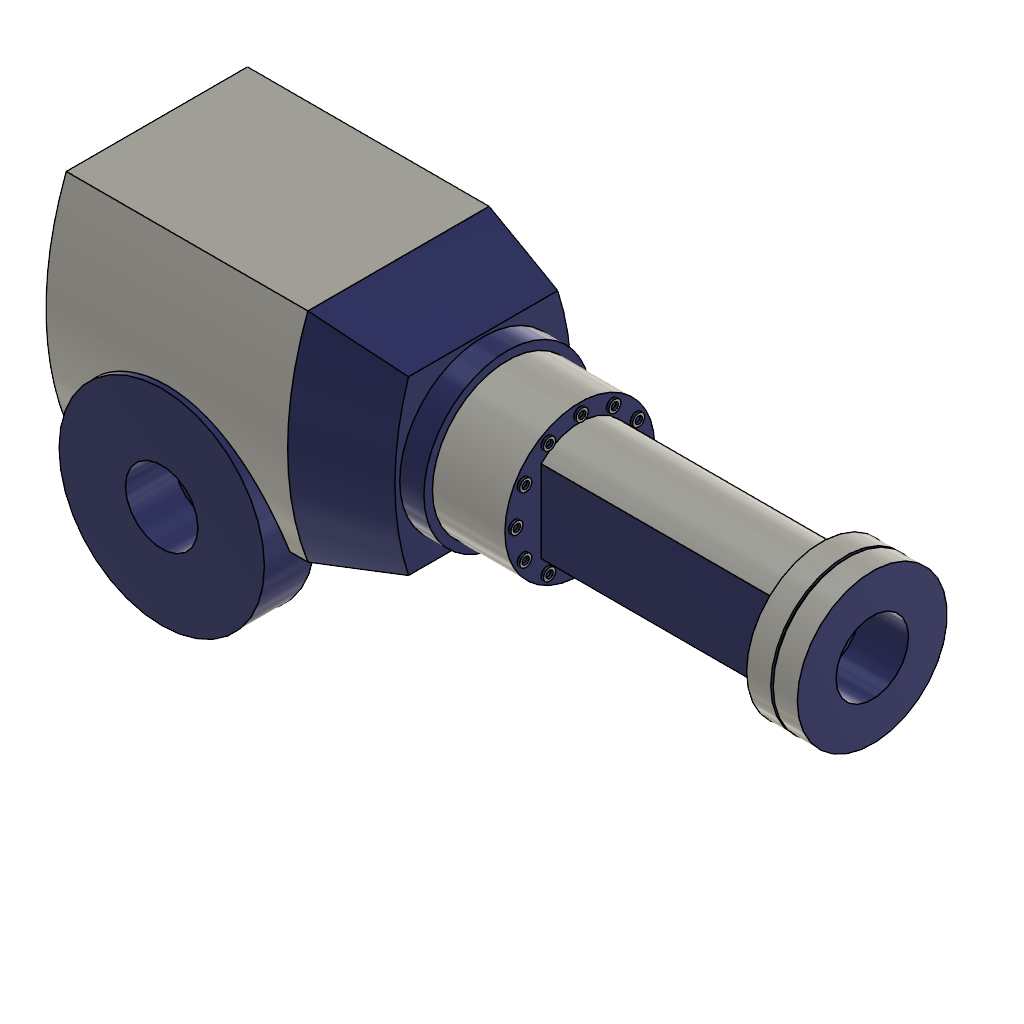
robotic_arm (Autodesk Fusion 360 archive; units mm, degrees)
design "jaw3"
part number: 2026-11-17-13-22-34-875
Autodesk Fusion 360 part; units mm, degrees
(part 1 of 2)
sketch "Esquisse1" plane through (0, 0, 0) normal (1, 0, 0) x (0, 1, 0)
  line L0 (0, 0) -> (0, 45)
  line L1 (0, 0) -> (0, -45)
  line L2 (0, 45) -> (37.5, 45)
  line L3 (0, 45) -> (-37.5, 45)
  line L4 (0, -45) -> (37.5, -45)
  line L5 (0, -45) -> (-37.5, -45)
  arc A0 (-37.5, 45) -> (-37.5, -45) centre (79.119, 0) ccw
  line L6 (0, 1.75) -> (0, 22.5)
  arc A1 (37.5, -45) -> (37.5, 45) centre (-79.119, 0) ccw
  dimension "d1" = 45
  dimension "d2" = 45
  dimension "d3" = 37.5
  dimension "d4" = 37.5
  dimension "d5" = 37.5
  dimension "d6" = 37.5
  dimension "d7" = 125
  constraint coincident L0.start L1.start
  constraint vertical L0
  constraint parallel L0 L1
  constraint perpendicular L0 L2
  constraint perpendicular L0 L3
  constraint perpendicular L1 L4
  constraint perpendicular L1 L5
  constraint symmetric L3.end L6 L2.end
  constraint symmetric L5.end L6 L4.end
  constraint symmetric A0 L6 A1
  measures "d1" distance of L0.start L0.end
  measures "d2" distance of L0.start L1.end
  measures "d3" distance of L0.end L2.end
  measures "d4" distance of L0.end L3.end
  measures "d5" distance of L1.end L4.end
  measures "d6" distance of L1.end L5.end
  measures "d7" radius of A0
extrude "Extrusion1" add sketch "Esquisse1" along normal blind 100
extrude "Extrusion2" add 1 faces at (100, -15.1807, -3.0661) along direction (1, 0, 0) blind 35 draft -15
sketch "Esquisse2" plane through (135, 0, 0) normal (1, 0, 0) x (0, 1, 0)
  line L0 (-30.8786, -35.6218) -> (30.8786, -35.6218)
  arc A0 (30.8786, -35.6218) -> (30.8786, 35.6218) centre (-79.119, 0) ccw
  line L1 (30.8786, 35.6218) -> (-30.8786, 35.6218)
  arc A1 (-30.8786, 35.6218) -> (-30.8786, -35.6218) centre (79.119, 0) ccw
  circle A2 centre (0, 0) radius 34.5
  dimension "d12" = 69
  constraint coincident A2.centre origin
  measures "d12" diameter of A2
extrude "Extrusion3" add sketch "Esquisse2" along normal blind 10 contours A2
sketch "Esquisse3" plane through (145, 0, 0) normal (1, 0, 0) x (0, 1, 0)
  circle A0 centre (0, 0) radius 34.5
  circle A1 centre (0, 0) radius 31
  dimension "d15" = 62
  constraint concentric A0 A1
  measures "d15" diameter of A1
extrude "Extrusion4" add sketch "Esquisse3" along normal blind 30 contours A1
sketch "Esquisse4" plane through (175, 0, 0) normal (1, 0, 0) x (0, 1, 0)
  circle A0 centre (0, 0) radius 31
  line L0 (0, 0) -> (27, 0) construction
  circle A1 centre (27, 0) radius 2.5
  circle A2 centre (27, 0) radius 1.5
  dimension "d18" = 27
  dimension "d19" = 5
  dimension "d20" = -1
  constraint coincident A0.centre L0.start
  constraint horizontal L0
  constraint coincident L0.end A1.centre
  measures "d18" distance of A0.centre L0.end
  measures "d19" diameter of A1
extrude "Extrusion5" add sketch "Esquisse4" along normal blind 1 contours A1
pattern_circular "Réseau C1" count 12 over 360 about axis through (175, 0, 0) along (1, 0, 0) of "Extrusion5"
sketch "Esquisse5" plane through (175, 0, 0) normal (1, 0, 0) x (0, 1, 0)
  circle A0 centre (27, 0) radius 2.5
  circle A1 centre (0, 0) radius 31
  circle A2 centre (23.3827, 13.5) radius 2.5
  circle A3 centre (13.5, 23.3827) radius 2.5
  circle A4 centre (0, 27) radius 2.5
  circle A5 centre (-13.5, 23.3827) radius 2.5
  circle A6 centre (-23.3827, 13.5) radius 2.5
  circle A7 centre (-27, 0) radius 2.5
  circle A8 centre (-23.3827, -13.5) radius 2.5
  circle A9 centre (-13.5, -23.3827) radius 2.5
  circle A10 centre (0, -27) radius 2.5
  circle A11 centre (13.5, -23.3827) radius 2.5
  circle A12 centre (23.3827, -13.5) radius 2.5
  line L0 (0, 0) -> (16, 0)
  line L1 (16, 0) -> (16, 17)
  line L2 (16, 0) -> (16, -17)
  line L3 (0, 1.75) -> (0, 22.5)
  line L4 (-16, 0) -> (-16, 17)
  line L5 (-16, 0) -> (-16, -17)
  arc A13 (16, 17) -> (-16, 17) centre (0, 1.9003) ccw
  line L6 (1.75, 0) -> (22.5, 0)
  arc A14 (-16, -17) -> (16, -17) centre (0, -1.9003) ccw
  dimension "d25" = 16
  dimension "d26" = 17
  dimension "d27" = 17
  dimension "d28" = 22
  constraint coincident A1.centre L0.start
  constraint horizontal L0
  constraint perpendicular L0 L1
  constraint perpendicular L0 L2
  constraint symmetric L0.end L3 L4.start
  constraint symmetric L1.end L3 L4.end
  constraint symmetric L2.end L3 L5.end
  constraint symmetric L1.end L6 L2.end
  constraint symmetric L4.end L6 L5.end
  constraint symmetric A13 L6 A14
  measures "d25" distance of A1.centre L0.end
  measures "d26" distance of L0.end L1.end
  measures "d27" distance of L0.end L2.end
  measures "d28" radius of A13
extrude "Extrusion6" add sketch "Esquisse5" along normal blind 100 contours L1 L2 L4 L5 A13 A14
sketch "Esquisse6" plane through (275, 0, 0) normal (1, 0, 0) x (0, 1, 0)
  line L0 (-16, 17) -> (-16, -17)
  arc A0 (-16, -17) -> (16, -17) centre (0, -1.9003) ccw
  line L1 (16, -17) -> (16, 17)
  arc A1 (16, 17) -> (-16, 17) centre (0, 1.9003) ccw
  circle A2 centre (0, 0) radius 31
extrude "Extrusion7" add sketch "Esquisse6" along normal blind 10 contours L0 A0 L1 A1 | A2
sketch "Esquisse7" plane through (285, 0, 0) normal (1, 0, 0) x (0, 1, 0)
  circle A0 centre (0, 0) radius 31
  circle A1 centre (0, 0) radius 30
  dimension "d33" = -1
extrude "Extrusion8" add sketch "Esquisse7" along normal blind 1 contours A1
sketch "Esquisse8" plane through (286, 0, 0) normal (1, 0, 0) x (0, 1, 0)
  circle A0 centre (0, 0) radius 30
  circle A1 centre (0, 0) radius 31
  dimension "d36" = 62
  constraint concentric A0 A1
  measures "d36" diameter of A1
extrude "Extrusion9" add sketch "Esquisse8" along normal blind 10 contours A0 | A1
ref_plane "Plan de construction1" through (0, -37.5, 45) normal (0, -1, 0) x (1, 0, 0)
sketch "Esquisse9" plane through (0, -37.5, 0) normal (0, -1, 0) x (-1, 0, 0)
  circle A0 centre (-50, 45) radius 42.5
  dimension "d40" = 85
  measures "d40" diameter of A0
extrude "Extrusion10" add sketch "Esquisse9" along normal mid plane 21
sketch "Esquisse10" plane through (0, -27, 0) normal (0, 1, 0) x (-1, 0, 0)
  line L0 (-7.5, -45) -> (-92.5, -45)
  arc A0 (-92.5, -45) -> (-7.5, -45) centre (-50, -45) ccw
  line L1 (-50, -45) -> (-50, -75) construction
  line L2 (-70, -45) -> (-70, -68.0897)
  line L3 (-30, -45) -> (-30, -68.0897)
  arc A1 (-70, -68.0897) -> (-30, -68.0897) centre (-50, -45.729) ccw
  dimension "d43" = 30
  dimension "d44" = 20
  dimension "d45" = -20
  dimension "d46" = 30
  constraint coincident A0.centre L1.start
  constraint perpendicular L0 L1
  measures "d43" distance of A0.centre L1.end
  measures "d46" radius of A1
extrude "Extrusion11" add sketch "Esquisse10" along normal blind 35 contours L0 L2 L3 A1
sketch "Esquisse11" plane through (70, 0, 0) normal (1, 0, 0) x (0, 1, 0)
  line L0 (-27, -45) -> (-27, -68.0897)
  line L1 (-27, -68.0897) -> (8, -68.0897)
  line L2 (8, -68.0897) -> (8, -45)
  line L3 (8, -45) -> (-27, -45)
  line L4 (8, -45) -> (33, -45)
  line L5 (8, -45) -> (8, -87)
  arc A0 (8, -87) -> (33, -45) centre (-21.8393, -40.7981) ccw
  dimension "d49" = 25
  dimension "d50" = 42
  dimension "d51" = 55
  constraint coincident L2.end L3.start
  constraint perpendicular L2 L4
  constraint perpendicular L3 L5
  measures "d49" distance of L2.end L4.end
  measures "d50" distance of L2.end L5.end
  measures "d51" radius of A0
extrude "Extrusion12" add sketch "Esquisse11" against normal blind 40 contours L2 L4 L5 A0
delete_face "DeleteFace1" 1 faces at (50, 8, -83.243)
sketch "Esquisse12" plane through (296, 0, 0) normal (1, 0, 0) x (0, 1, 0)
  circle A0 centre (0, 0) radius 31
  circle A1 centre (0, 0) radius 15
  dimension "d54" = 30
  constraint coincident A0.centre A1.centre
  measures "d54" diameter of A1
extrude "Extrusion13" cut sketch "Esquisse12" against normal blind 20 contours A1
sketch "Esquisse13" plane through (0, -48, 0) normal (0, -1, 0) x (1, 0, 0)
  circle A0 centre (50, -45) radius 42.5
  circle A1 centre (50, -45) radius 15
  dimension "d57" = 30
  constraint concentric A0 A1
  measures "d57" diameter of A1
extrude "Extrusion14" cut sketch "Esquisse13" against normal blind 20 contours A1
equation "d41 = ( 21 / 2 ) * 1 mm"

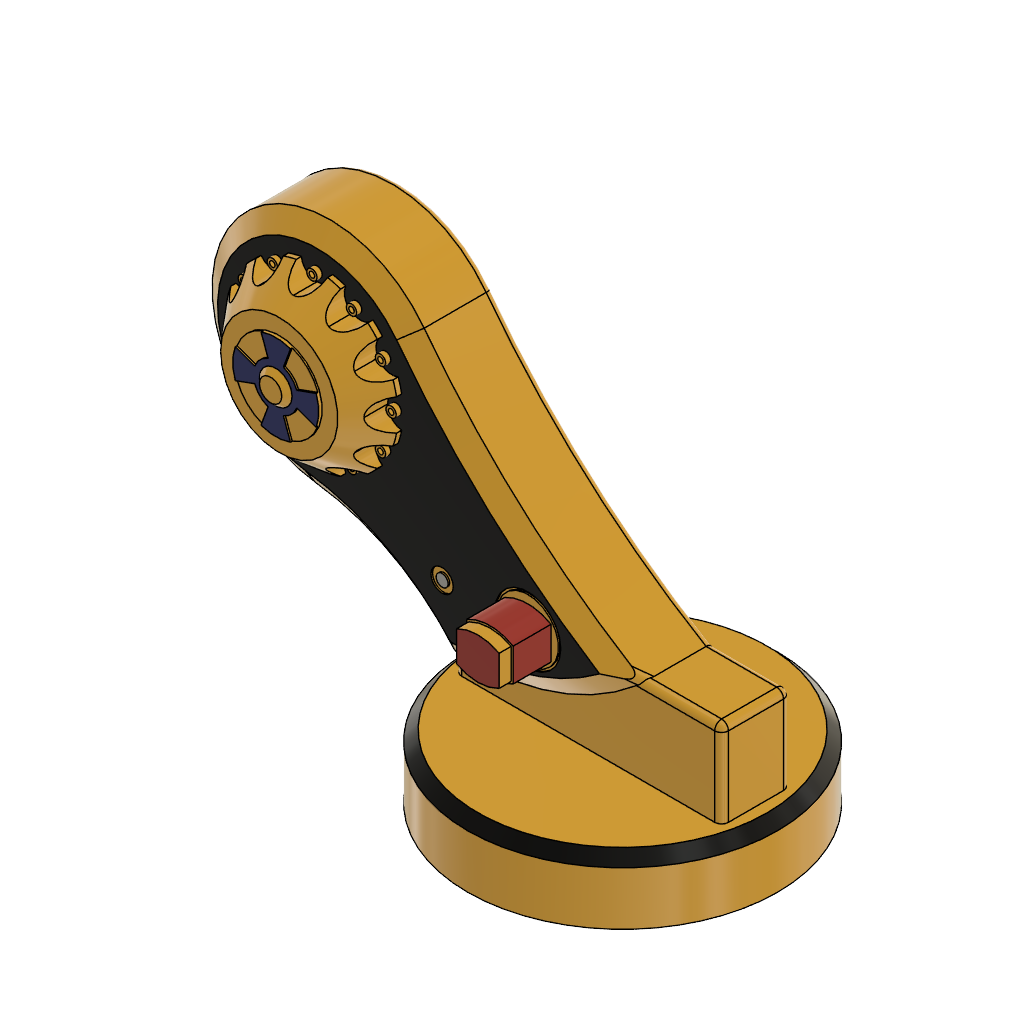
design "jaw"
part number: 2026-11-15-23-48-15-800
Autodesk Fusion 360 part; units mm, degrees
sketch "Esquisse8" plane through (0, 0, 0) normal (0, 0, 1) x (1, 0, 0)
  circle A0 centre (0, 0) radius 90
  dimension "d25" = 180
  constraint coincident A0.centre origin
  measures "d25" diameter of A0
extrude "Extrusion4" add sketch "Esquisse8" along normal blind 37
chamfer "Chanfrein2" distance 6 angle 45 1 edges at (-83.9095, -32.5454, 37) tangent chain off
sketch "Esquisse9" plane through (0, 0, 37) normal (0, 0, 1) x (-1, 0, 0)
  circle A0 centre (0, 0) radius 84
  line L0 (-77.5, 20) -> (77.5, 20)
  line L1 (77.5, 20) -> (77.5, -20)
  line L2 (77.5, -20) -> (-77.5, -20)
  line L3 (-77.5, -20) -> (-77.5, 20)
  line L4 (-77.5, 20) -> (77.5, -20) construction
  line L5 (77.5, 20) -> (-77.5, -20) construction
  dimension "d29" = 155
  dimension "d30" = 40
  constraint horizontal L0
  constraint perpendicular L0 L1
  constraint parallel L0 L2
  constraint parallel L1 L3
  constraint coincident L4 A0.centre
  constraint coincident L5 A0.centre
  constraint coincident A0.centre origin
  measures "d29" distance of L1.end L2.end
  measures "d30" distance of L0.end L1.end
extrude "Extrusion5" add sketch "Esquisse9" along normal blind 50 contours L0 L1 L2 L3
sketch "Esquisse10" plane through (0, -20, 0) normal (0, -1, 0) x (1, 0, 0)
  line L0 (-77.5, 37) -> (77.5, 37)
  line L1 (77.5, 37) -> (77.5, 87)
  line L2 (77.5, 87) -> (-77.5, 87)
  line L3 (-77.5, 87) -> (-77.5, 37)
  line L4 (-77.5, 87) -> (32.5, 87)
  line L5 (-77.5, 87) -> (-77.5, 48)
  arc A0 (-77.5, 48) -> (32.5, 87) centre (-68.6761, 197.7402) ccw
  dimension "d33" = 110
  dimension "d34" = 39
  dimension "d36" = 150
  constraint coincident L2.end L3.start
  constraint perpendicular L3 L4
  constraint perpendicular L2 L5
  measures "d33" distance of L2.end L4.end
  measures "d34" distance of L2.end L5.end
  measures "d36" radius of A0
extrude "Extrusion6" cut sketch "Esquisse10" against normal blind 125 contours L2 L3 L4 L5 A0
sketch "Esquisse12" plane through (0, 0, 0) normal (0, 1, 0) x (1, 0, 0)
  line L0 (0, 0) -> (-150, 0)
  line L1 (-150, 0) -> (-150, -160)
  circle A0 centre (-150, -160) radius 68.5
  arc A1 (32.5, -87) -> (-77.5, -48) centre (-68.6761, -197.7402) ccw
  arc A2 (-158.3154, -92.0066) -> (-77.5, -48) centre (-173.4894, 32.069) ccw
  arc A3 (32.5, -87) -> (-95.2795, -201.2057) centre (256.2101, -465.8849) ccw
  dimension "d39" = 150
  dimension "d40" = 160
  dimension "d41" = 137
  dimension "d42" = 125
  dimension "d43" = 440
  constraint coincident L0.start origin
  constraint horizontal L0
  constraint perpendicular L0 L1
  constraint coincident L1.end A0.centre
  constraint tangent A0 A2
  constraint coincident A1.end A2.end
  constraint coincident A0 A2.start
  constraint coincident A1.start A3.start
  constraint coincident A0 A3.end
  constraint tangent A0 A3
  measures "d39" distance of L0.start L0.end
  measures "d40" distance of L0.end L1.end
  measures "d41" diameter of A0
  measures "d42" radius of A2
  measures "d43" radius of A3
extrude "Extrusion9" add sketch "Esquisse12" along normal mid plane 40
sketch "Esquisse14" plane through (0, -20, 0) normal (0, -1, 0) x (1, 0, 0)
  line L0 (-77.5, 48) -> (-77.5, 37)
  line L1 (-77.5, 37) -> (77.5, 37)
  line L2 (77.5, 37) -> (77.5, 87)
  line L3 (77.5, 87) -> (32.5, 87)
  arc A0 (-95.2795, 201.2057) -> (32.5, 87) centre (256.2101, 465.8849) ccw
  arc A1 (-95.2795, 201.2057) -> (-158.3154, 92.0066) centre (-150, 160) ccw
  arc A2 (-77.5, 48) -> (-158.3154, 92.0066) centre (-173.4894, -32.069) ccw
  circle A3 centre (-150, 160) radius 68.5
  arc A4 (-77.5, 48) -> (32.5, 87) centre (-68.6761, 197.7402) ccw
  arc A5 (-95.2795, 201.2057) -> (32.5, 87) centre (256.2101, 465.8849) ccw
  arc A6 (-77.5, 48) -> (-158.3154, 92.0066) centre (-173.4894, -32.069) ccw
extrude "Extrusion10" add sketch "Esquisse14" along normal blind 7.5 draft -55 contours A0 A2 A3 A4 A5 A6 | A1 A3
sketch "Esquisse15" plane through (0, -27.5, 0) normal (0, -1, 0) x (1, 0, 0)
  arc A0 (-103.8359, 194.7625) -> (-157.0151, 102.6385) centre (-150, 160) ccw
  arc A1 (-72.4228, 58.5017) -> (-157.0151, 102.6385) centre (-173.4894, -32.069) ccw
  arc A2 (-72.4228, 58.5017) -> (14.1053, 85.7195) centre (-68.6761, 197.7402) ccw
  arc A3 (-103.8359, 194.7625) -> (14.1053, 85.7195) centre (256.2101, 465.8849) ccw
  circle A4 centre (-150, 160) radius 50
  dimension "d52" = 100
  constraint concentric A0 A4
  measures "d52" diameter of A4
extrude "Extrusion11" add sketch "Esquisse15" along normal blind 3 contours A4
extrude "Extrusion12" add 1 faces at (-167.3965, -30.5, 167.9656) along direction (0, -1, 0) blind 19 draft -40
sketch "Esquisse18" plane through (0, -49.5, 0) normal (0, -1, 0) x (1, 0, 0)
  circle A0 centre (-150, 160) radius 34.0571
  circle A1 centre (-150, 160) radius 50
  line L0 (-150, 160) -> (-150, 210)
  arc A2 (-159.1254, 209.1602) -> (-150, 201) centre (-150.1645, 209.9985) ccw
  arc A3 (-150, 201) -> (-140.8746, 209.1602) centre (-149.8355, 209.9985) ccw
  dimension "d62" = 9
  dimension "d63" = 9
  constraint coincident A0.centre A1.centre
  constraint coincident A1 L0.end
  constraint vertical L0
  constraint coincident A1 A2.start
  constraint coincident L0 A2.end
  constraint symmetric L0 A2.end A3.start
  constraint symmetric L0 A2.start A3.end
  constraint symmetric L0 A2 A3
  measures "d62" distance of L0.end A2.end
  measures "d63" radius of A2
extrude "Extrusion13" cut sketch "Esquisse18" against normal up to surface (22 mm away) contours A1 L0 A3 | A1 L0 A2
sketch "Esquisse19" plane through (0, -27.5, 0) normal (0, -1, 0) x (1, 0, 0)
  arc A0 (-159.1254, 209.1602) -> (-140.8746, 209.1602) centre (-150, 160) ccw
  arc A1 (-159.1254, 209.1602) -> (-150, 201) centre (-150.1645, 209.9985) ccw
  arc A2 (-150, 201) -> (-140.8746, 209.1602) centre (-149.8355, 209.9985) ccw
  arc A3 (-103.8359, 194.7625) -> (-157.0151, 102.6385) centre (-150, 160) ccw
  arc A4 (-72.4228, 58.5017) -> (-157.0151, 102.6385) centre (-173.4894, -32.069) ccw
  arc A5 (-72.4228, 58.5017) -> (14.1053, 85.7195) centre (-68.6761, 197.7402) ccw
  arc A6 (-103.8359, 194.7625) -> (14.1053, 85.7195) centre (256.2101, 465.8849) ccw
  line L0 (-150, 201) -> (-150, 217.7889)
  circle A7 centre (-150, 206) radius 3
  circle A8 centre (-150, 206) radius 1.6
  dimension "d66" = 6
  dimension "d67" = -1.4
  constraint coincident A1.end A2.start
  constraint coincident A3 L0.end
  constraint perpendicular A3 L0
  constraint coincident L0 A7.centre
  measures "d66" diameter of A7
extrude "Extrusion14" add sketch "Esquisse19" along normal blind 3 contours L0 A7 A8 | L0 A7 A8
pattern_circular "Réseau C1" count 12 over 360 about axis through (-150, -49.5, 160) along (0, 1, 0) of "Extrusion13", "Extrusion14"
sketch "Esquisse21" plane through (0, -49.5, 0) normal (0, -1, 0) x (1, 0, 0)
  circle A0 centre (-150, 160) radius 34.0571
  circle A1 centre (-150, 160) radius 13
  circle A2 centre (-150, 160) radius 25
  dimension "d72" = 26
  dimension "d73" = 50
  constraint concentric A0 A1
  constraint concentric A1 A2
  measures "d72" diameter of A1
  measures "d73" diameter of A2
extrude "Extrusion15" add sketch "Esquisse21" along normal blind 1 contours A1 | A2
sketch "Esquisse22" plane through (0, -50.5, 0) normal (0, -1, 0) x (1, 0, 0)
  circle A0 centre (-150, 160) radius 25
  circle A1 centre (-150, 160) radius 13
  line L0 (-149.9924, 173) -> (-149.9855, 185) construction
  line L1 (-158.5368, 183.4973) -> (-154.4392, 172.2186)
  line L2 (-141.4358, 183.4873) -> (-145.5466, 172.2134)
  line L3 (-173.4973, 151.4632) -> (-162.2186, 155.5608)
  line L4 (-173.4873, 168.5642) -> (-162.2134, 164.4534)
  line L5 (-141.4632, 136.5027) -> (-145.5608, 147.7814)
  line L6 (-158.5642, 136.5127) -> (-154.4534, 147.7866)
  line L7 (-126.5027, 168.5368) -> (-137.7814, 164.4392)
  line L8 (-126.5127, 151.4358) -> (-137.7866, 155.5466)
  dimension "d76" = 26
  dimension "d77" = 20
  dimension "d79" = 360
  constraint concentric A0 A1
  constraint coincident A1 L0.start
  constraint coincident A0 L0.end
  constraint perpendicular A0 L0
  constraint coincident A0 L1.start
  constraint coincident A1 L1.end
  constraint perpendicular A1 L1
  constraint symmetric L0 L1.start L2.start
  constraint symmetric L0 L1.end L2.end
  measures "d76" diameter of A1
  measures "d77" angle of L0 L1
extrude "Extrusion16" add sketch "Esquisse22" along normal blind 1 contours A0 A1 L7 L8 | A0 A1 L1 L2 | A1 | A0 A1 L5 L6 | A0 A1 L3 L4
sketch "Esquisse23" plane through (0, -51.5, 0) normal (0, -1, 0) x (1, 0, 0)
  line L0 (-126.5027, 168.5368) -> (-137.7814, 164.4392)
  arc A0 (-137.7814, 164.4392) -> (-145.5466, 172.2134) centre (-150, 160) ccw
  line L1 (-145.5466, 172.2134) -> (-141.4358, 183.4873)
  arc A1 (-141.4358, 183.4873) -> (-158.5368, 183.4973) centre (-150, 160) ccw
  line L2 (-158.5368, 183.4973) -> (-154.4392, 172.2186)
  arc A2 (-154.4392, 172.2186) -> (-162.2134, 164.4534) centre (-150, 160) ccw
  line L3 (-162.2134, 164.4534) -> (-173.4873, 168.5642)
  arc A3 (-173.4873, 168.5642) -> (-173.4973, 151.4632) centre (-150, 160) ccw
  line L4 (-173.4973, 151.4632) -> (-162.2186, 155.5608)
  arc A4 (-162.2186, 155.5608) -> (-154.4534, 147.7866) centre (-150, 160) ccw
  line L5 (-154.4534, 147.7866) -> (-158.5642, 136.5127)
  arc A5 (-158.5642, 136.5127) -> (-141.4632, 136.5027) centre (-150, 160) ccw
  line L6 (-141.4632, 136.5027) -> (-145.5608, 147.7814)
  arc A6 (-145.5608, 147.7814) -> (-137.7866, 155.5466) centre (-150, 160) ccw
  line L7 (-137.7866, 155.5466) -> (-126.5127, 151.4358)
  arc A7 (-126.5127, 151.4358) -> (-126.5027, 168.5368) centre (-150, 160) ccw
  circle A8 centre (-150, 160) radius 9.5
  dimension "d82" = 19
  constraint concentric A0 A8
  measures "d82" diameter of A8
extrude "Extrusion17" add sketch "Esquisse23" along normal blind 3 draft -45 contours A8
sketch "Esquisse24" plane through (0, -27.5, 0) normal (0, -1, 0) x (1, 0, 0)
  circle A0 centre (-150, 206) radius 3
  arc A1 (-133.3227, 207.1367) -> (-140.8746, 209.1602) centre (-150, 160) ccw
  arc A2 (-133.3227, 207.1367) -> (-129.5, 195.507) centre (-125.1432, 203.3822) ccw
  arc A3 (-129.5, 195.507) -> (-117.5171, 198.0113) centre (-124.8583, 203.2177) ccw
  arc A4 (-111.9887, 192.4829) -> (-117.5171, 198.0113) centre (-150, 160) ccw
  arc A5 (-111.9887, 192.4829) -> (-114.493, 180.5) centre (-106.7823, 185.1417) ccw
  arc A6 (-114.493, 180.5) -> (-102.8633, 176.6773) centre (-106.6178, 184.8568) ccw
  arc A7 (-100.8398, 169.1254) -> (-102.8633, 176.6773) centre (-150, 160) ccw
  arc A8 (-100.8398, 169.1254) -> (-109, 160) centre (-100.0015, 160.1645) ccw
  arc A9 (-109, 160) -> (-100.8398, 150.8746) centre (-100.0015, 159.8355) ccw
  arc A10 (-102.8633, 143.3227) -> (-100.8398, 150.8746) centre (-150, 160) ccw
  arc A11 (-102.8633, 143.3227) -> (-114.493, 139.5) centre (-106.6178, 135.1432) ccw
  arc A12 (-114.493, 139.5) -> (-111.9887, 127.5171) centre (-106.7823, 134.8583) ccw
  arc A13 (-117.5171, 121.9887) -> (-111.9887, 127.5171) centre (-150, 160) ccw
  arc A14 (-117.5171, 121.9887) -> (-129.5, 124.493) centre (-124.8583, 116.7823) ccw
  arc A15 (-129.5, 124.493) -> (-133.3227, 112.8633) centre (-125.1432, 116.6178) ccw
  arc A16 (-140.8746, 110.8398) -> (-133.3227, 112.8633) centre (-150, 160) ccw
  arc A17 (-140.8746, 110.8398) -> (-150, 119) centre (-149.8355, 110.0015) ccw
  arc A18 (-150, 119) -> (-159.1254, 110.8398) centre (-150.1645, 110.0015) ccw
  arc A19 (-166.6773, 112.8633) -> (-159.1254, 110.8398) centre (-150, 160) ccw
  arc A20 (-166.6773, 112.8633) -> (-170.5, 124.493) centre (-174.8568, 116.6178) ccw
  arc A21 (-170.5, 124.493) -> (-182.4829, 121.9887) centre (-175.1417, 116.7823) ccw
  arc A22 (-188.0113, 127.5171) -> (-182.4829, 121.9887) centre (-150, 160) ccw
  arc A23 (-188.0113, 127.5171) -> (-185.507, 139.5) centre (-193.2177, 134.8583) ccw
  arc A24 (-185.507, 139.5) -> (-197.1367, 143.3227) centre (-193.3822, 135.1432) ccw
  arc A25 (-199.1602, 150.8746) -> (-197.1367, 143.3227) centre (-150, 160) ccw
  arc A26 (-199.1602, 150.8746) -> (-191, 160) centre (-199.9985, 159.8355) ccw
  arc A27 (-191, 160) -> (-199.1602, 169.1254) centre (-199.9985, 160.1645) ccw
  arc A28 (-197.1367, 176.6773) -> (-199.1602, 169.1254) centre (-150, 160) ccw
  arc A29 (-197.1367, 176.6773) -> (-185.507, 180.5) centre (-193.3822, 184.8568) ccw
  arc A30 (-185.507, 180.5) -> (-188.0113, 192.4829) centre (-193.2177, 185.1417) ccw
  arc A31 (-182.4829, 198.0113) -> (-188.0113, 192.4829) centre (-150, 160) ccw
  arc A32 (-182.4829, 198.0113) -> (-170.5, 195.507) centre (-175.1417, 203.2177) ccw
  arc A33 (-170.5, 195.507) -> (-166.6773, 207.1367) centre (-174.8568, 203.3822) ccw
  arc A34 (-159.1254, 209.1602) -> (-166.6773, 207.1367) centre (-150, 160) ccw
  arc A35 (-159.1254, 209.1602) -> (-150, 201) centre (-150.1645, 209.9985) ccw
  arc A36 (-150, 201) -> (-140.8746, 209.1602) centre (-149.8355, 209.9985) ccw
  arc A37 (-103.8359, 194.7625) -> (-157.0151, 102.6385) centre (-150, 160) ccw
  arc A38 (-72.4228, 58.5017) -> (-157.0151, 102.6385) centre (-173.4894, -32.069) ccw
  arc A39 (-72.4228, 58.5017) -> (14.1053, 85.7195) centre (-68.6761, 197.7402) ccw
  arc A40 (-103.8359, 194.7625) -> (14.1053, 85.7195) centre (256.2101, 465.8849) ccw
  circle A41 centre (-127, 199.8372) radius 3
  circle A42 centre (-110.1628, 183) radius 3
  circle A43 centre (-104, 160) radius 3
  circle A44 centre (-110.1628, 137) radius 3
  circle A45 centre (-127, 120.1628) radius 3
  circle A46 centre (-150, 114) radius 3
  circle A47 centre (-173, 120.1628) radius 3
  circle A48 centre (-189.8372, 137) radius 3
  circle A49 centre (-196, 160) radius 3
  circle A50 centre (-189.8372, 183) radius 3
  circle A51 centre (-173, 199.8372) radius 3
  line L0 (-41.0792, 96.5795) -> (-14.0792, 96.5795)
  line L1 (-14.0792, 96.5795) -> (-14.0792, 77.5795)
  line L2 (-14.0792, 77.5795) -> (-41.0792, 77.5795)
  line L3 (-41.0792, 77.5795) -> (-41.0792, 96.5795)
  arc A52 (-14.0792, 96.5795) -> (-41.0792, 96.5795) centre (-27.5792, 73.1968) ccw
  arc A53 (-41.0792, 77.5795) -> (-14.0792, 77.5795) centre (-27.5792, 100.9622) ccw
  dimension "d85" = 27
  dimension "d86" = 19
  dimension "d87" = 27
  dimension "d88" = 27
  constraint horizontal L0
  constraint vertical L1
  constraint horizontal L2
  constraint vertical L3
  measures "d85" distance of L0.start L0.end
  measures "d86" distance of L0.start L2.end
  measures "d87" radius of A53
  measures "d88" radius of A52
extrude "Extrusion18" add sketch "Esquisse24" along normal blind 22 contours L0 A52 | L0 L1 L2 L3 | L2 A53
sketch "Esquisse25" plane through (0, -49.5, 0) normal (0, -1, 0) x (1, 0, 0)
  arc A0 (-14.0792, 96.5795) -> (-41.0792, 96.5795) centre (-27.5792, 73.1968) ccw
  line L0 (-41.0792, 96.5795) -> (-41.0792, 77.5795)
  arc A1 (-41.0792, 77.5795) -> (-14.0792, 77.5795) centre (-27.5792, 100.9622) ccw
  line L1 (-14.0792, 77.5795) -> (-14.0792, 96.5795)
  line L2 (-15.2302, 78.2538) -> (-15.2302, 95.9053)
  arc A2 (-15.2302, 95.9053) -> (-39.9282, 95.9053) centre (-27.5792, 73.1968) ccw
  line L3 (-39.9282, 95.9053) -> (-39.9282, 78.2538)
  arc A3 (-39.9282, 78.2538) -> (-15.2302, 78.2538) centre (-27.5792, 100.9622) ccw
  dimension "d91" = -1.151
extrude "Extrusion19" add sketch "Esquisse25" along normal blind 7 contours L2 A2 L3 A3
sketch "Esquisse26" plane through (0, -27.5, 0) normal (0, -1, 0) x (1, 0, 0)
  circle A0 centre (-173, 199.8372) radius 3
  circle A1 centre (-189.8372, 183) radius 3
  circle A2 centre (-196, 160) radius 3
  circle A3 centre (-189.8372, 137) radius 3
  circle A4 centre (-173, 120.1628) radius 3
  circle A5 centre (-150, 114) radius 3
  circle A6 centre (-127, 120.1628) radius 3
  circle A7 centre (-110.1628, 137) radius 3
  circle A8 centre (-104, 160) radius 3
  circle A9 centre (-110.1628, 183) radius 3
  circle A10 centre (-127, 199.8372) radius 3
  arc A11 (-103.8359, 194.7625) -> (-157.0151, 102.6385) centre (-150, 160) ccw
  arc A12 (-72.4228, 58.5017) -> (-157.0151, 102.6385) centre (-173.4894, -32.069) ccw
  arc A13 (-72.4228, 58.5017) -> (14.1053, 85.7195) centre (-68.6761, 197.7402) ccw
  arc A14 (-103.8359, 194.7625) -> (14.1053, 85.7195) centre (256.2101, 465.8849) ccw
  arc A15 (-133.3227, 207.1367) -> (-140.8746, 209.1602) centre (-150, 160) ccw
  arc A16 (-133.3227, 207.1367) -> (-129.5, 195.507) centre (-125.1432, 203.3822) ccw
  arc A17 (-129.5, 195.507) -> (-117.5171, 198.0113) centre (-124.8583, 203.2177) ccw
  arc A18 (-111.9887, 192.4829) -> (-117.5171, 198.0113) centre (-150, 160) ccw
  arc A19 (-111.9887, 192.4829) -> (-114.493, 180.5) centre (-106.7823, 185.1417) ccw
  arc A20 (-114.493, 180.5) -> (-102.8633, 176.6773) centre (-106.6178, 184.8568) ccw
  arc A21 (-100.8398, 169.1254) -> (-102.8633, 176.6773) centre (-150, 160) ccw
  arc A22 (-100.8398, 169.1254) -> (-109, 160) centre (-100.0015, 160.1645) ccw
  arc A23 (-109, 160) -> (-100.8398, 150.8746) centre (-100.0015, 159.8355) ccw
  arc A24 (-102.8633, 143.3227) -> (-100.8398, 150.8746) centre (-150, 160) ccw
  arc A25 (-102.8633, 143.3227) -> (-114.493, 139.5) centre (-106.6178, 135.1432) ccw
  arc A26 (-114.493, 139.5) -> (-111.9887, 127.5171) centre (-106.7823, 134.8583) ccw
  arc A27 (-117.5171, 121.9887) -> (-111.9887, 127.5171) centre (-150, 160) ccw
  arc A28 (-117.5171, 121.9887) -> (-129.5, 124.493) centre (-124.8583, 116.7823) ccw
  arc A29 (-129.5, 124.493) -> (-133.3227, 112.8633) centre (-125.1432, 116.6178) ccw
  arc A30 (-140.8746, 110.8398) -> (-133.3227, 112.8633) centre (-150, 160) ccw
  arc A31 (-140.8746, 110.8398) -> (-150, 119) centre (-149.8355, 110.0015) ccw
  arc A32 (-150, 119) -> (-159.1254, 110.8398) centre (-150.1645, 110.0015) ccw
  arc A33 (-166.6773, 112.8633) -> (-159.1254, 110.8398) centre (-150, 160) ccw
  arc A34 (-166.6773, 112.8633) -> (-170.5, 124.493) centre (-174.8568, 116.6178) ccw
  arc A35 (-170.5, 124.493) -> (-182.4829, 121.9887) centre (-175.1417, 116.7823) ccw
  arc A36 (-188.0113, 127.5171) -> (-182.4829, 121.9887) centre (-150, 160) ccw
  arc A37 (-188.0113, 127.5171) -> (-185.507, 139.5) centre (-193.2177, 134.8583) ccw
  arc A38 (-185.507, 139.5) -> (-197.1367, 143.3227) centre (-193.3822, 135.1432) ccw
  arc A39 (-199.1602, 150.8746) -> (-197.1367, 143.3227) centre (-150, 160) ccw
  arc A40 (-199.1602, 150.8746) -> (-191, 160) centre (-199.9985, 159.8355) ccw
  arc A41 (-191, 160) -> (-199.1602, 169.1254) centre (-199.9985, 160.1645) ccw
  arc A42 (-197.1367, 176.6773) -> (-199.1602, 169.1254) centre (-150, 160) ccw
  arc A43 (-197.1367, 176.6773) -> (-185.507, 180.5) centre (-193.3822, 184.8568) ccw
  arc A44 (-185.507, 180.5) -> (-188.0113, 192.4829) centre (-193.2177, 185.1417) ccw
  arc A45 (-182.4829, 198.0113) -> (-188.0113, 192.4829) centre (-150, 160) ccw
  arc A46 (-182.4829, 198.0113) -> (-170.5, 195.507) centre (-175.1417, 203.2177) ccw
  arc A47 (-170.5, 195.507) -> (-166.6773, 207.1367) centre (-174.8568, 203.3822) ccw
  arc A48 (-159.1254, 209.1602) -> (-166.6773, 207.1367) centre (-150, 160) ccw
  arc A49 (-159.1254, 209.1602) -> (-150, 201) centre (-150.1645, 209.9985) ccw
  arc A50 (-150, 201) -> (-140.8746, 209.1602) centre (-149.8355, 209.9985) ccw
  circle A51 centre (-150, 206) radius 3
  line L0 (-14.0792, 96.5795) -> (-14.0792, 77.5795)
  arc A52 (-41.0792, 77.5795) -> (-14.0792, 77.5795) centre (-27.5792, 100.9622) ccw
  line L1 (-41.0792, 77.5795) -> (-41.0792, 96.5795)
  arc A53 (-14.0792, 96.5795) -> (-41.0792, 96.5795) centre (-27.5792, 73.1968) ccw
  line L2 (-41.0792, 77.5795) -> (-14.0792, 96.5795)
  circle A54 centre (-27.5792, 87.0795) radius 17.857
  circle A55 centre (-27.5792, 87.0795) radius 19.1735
  line L3 (-27.5792, 87.0795) -> (-77.3464, 87.0795) construction
  circle A56 centre (-77.3464, 87.0795) radius 6.5
  circle A57 centre (-77.3464, 87.0795) radius 3.5
  dimension "d94" = 35.714
  dimension "d95" = 38.347
  dimension "d96" = 13
  dimension "d97" = 7
  constraint coincident A52.start L1.start
  constraint coincident L0.start A53.start
  constraint midpoint L2 A54.centre
  constraint concentric A54 A55
  constraint coincident A54.centre A55.centre
  constraint horizontal L3
  constraint coincident L3.end A56.centre
  measures "d94" diameter of A54
  measures "d95" diameter of A55
  measures "d96" diameter of A56
  measures "d97" diameter of A57
extrude "Extrusion20" cut sketch "Esquisse26" against normal blind 0.9 contours A55 | A56
sketch "Esquisse27" plane through (0, 0, 0) normal (0, 0, -1) x (1, 0, 0)
  circle A0 centre (0, 0) radius 90
  circle A1 centre (0, 0) radius 15
  dimension "d100" = 30
  constraint coincident A0.centre A1.centre
  measures "d100" diameter of A1
extrude "Extrusion21" cut sketch "Esquisse27" against normal blind 20 contours A1
fillet "Congé1" radius 4 10 edges at (55, -20, 87) (77.5, 0, 87) (77.5, -20, 62) (77.5, 20, 62) (55, 20, 87) (-113.7109, 20, 77.7105) (-209.3252, 20, 194.2458) (-37.0038, 20, 137.8215) (-77.5, 20, 42.5) (-77.5, -20, 42.5)
fillet "Congé2" radius 4 1 edges at (33.3618, -19.3305, 86.4926)
sketch "Esquisse28" plane through (0, 20, 0) normal (0, 1, 0) x (-1, 0, 0)
  line L0 (-73.5, 83) -> (-73.5, 37)
  line L1 (-73.5, 37) -> (73.5, 37)
  line L2 (73.5, 37) -> (73.5, 49.4364)
  arc A0 (157.8298, 95.977) -> (73.5, 49.4364) centre (173.4894, -32.069) ccw
  arc A1 (157.8298, 95.977) -> (98.4748, 198.7996) centre (150, 160) ccw
  arc A2 (-31.4099, 83) -> (98.4748, 198.7996) centre (-256.2101, 465.8849) ccw
  line L3 (-31.4099, 83) -> (-73.5, 83)
  circle A3 centre (150, 160) radius 15
  dimension "d107" = 30
  constraint concentric A1 A3
  measures "d107" diameter of A3
extrude "Extrusion22" cut sketch "Esquisse28" against normal blind 20 contours A3

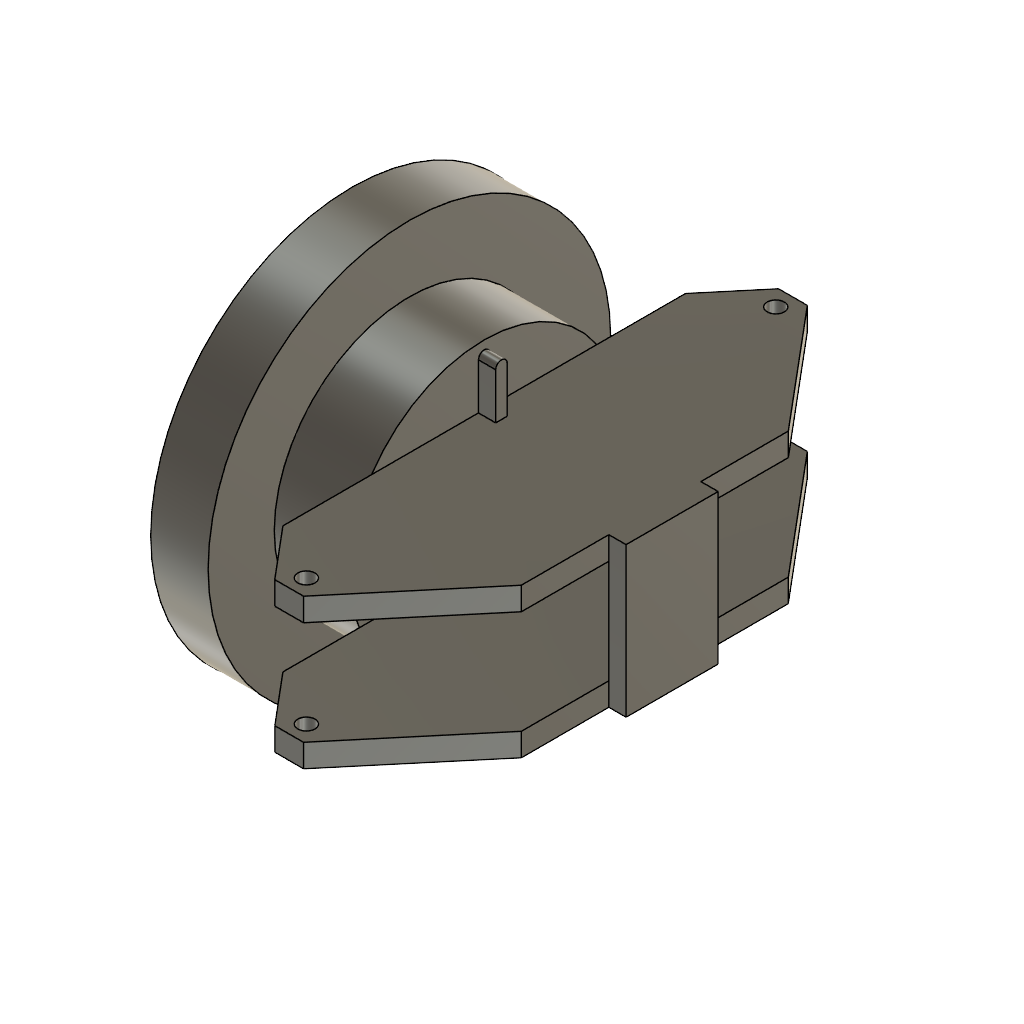
design "jaw6"
part number: 2026-11-18-08-03-36-471
Autodesk Fusion 360 part; units mm, degrees
sketch "Esquisse1" plane through (0, 0, 0) normal (1, 0, 0) x (0, 1, 0)
  circle A0 centre (0, 0) radius 35
  dimension "d1" = 70
  constraint coincident A0.centre origin
  measures "d1" diameter of A0
extrude "Extrusion1" add sketch "Esquisse1" along normal blind 10
sketch "Esquisse2" plane through (10, 0, 0) normal (1, 0, 0) x (0, 1, 0)
  circle A0 centre (0, 0) radius 35
  circle A1 centre (0, 0) radius 23.5
  dimension "d4" = 47
  constraint coincident A0.centre A1.centre
  measures "d4" diameter of A1
extrude "Extrusion2" add sketch "Esquisse2" along normal blind 13 contours A1
ref_plane "Plan de construction1" through (0, 0, 13) normal (0, 0, 1) x (1, 0, 0)
sketch "Esquisse3" plane through (0, 0, 13) normal (0, 0, 1) x (1, 0, 0)
  line L0 (23, 0) -> (23, -35)
  line L1 (23, -35) -> (30.3921, -43.8095)
  line L2 (30.3921, -43.8095) -> (35.3921, -43.8095)
  line L3 (23, 0) -> (52.6735, 0)
  line L4 (35.3921, -43.8095) -> (52.6735, -23.2143)
  line L5 (35.3921, -43.8095) -> (51.7524, -43.8095)
  line L6 (52.6735, -23.2143) -> (52.6735, 0)
  line L7 (23, 35) -> (30.3921, 43.8095)
  line L8 (30.3921, 43.8095) -> (35.3921, 43.8095)
  line L9 (35.3921, 43.8095) -> (52.6735, 23.2143)
  line L10 (52.6735, 23.2143) -> (52.6735, 0)
  line L11 (23, 0) -> (23, 35)
  dimension "d9" = 35
  dimension "d11" = 11.5
  dimension "d13" = 5
  dimension "d14" = 50
  constraint vertical L0
  constraint horizontal L2
  constraint perpendicular L0 L3
  constraint parallel L2 L5
  constraint perpendicular L3 L6
  constraint symmetric L0.start L3 L11.start
  constraint symmetric L0.end L3 L7.start
  constraint symmetric L1.end L3 L7.end
  constraint symmetric L2.end L3 L8.end
  constraint symmetric L3 L4.end L9.end
  measures "d9" distance of L0.start L0.end
  measures "d11" distance of L0.end L1.end
  measures "d13" distance of L1.end L2.end
  measures "d14" angle of L4 L5
extrude "Extrusion3" add sketch "Esquisse3" against normal blind 4
sketch "Esquisse4" plane through (0, 0, 13) normal (0, 0, 1) x (-1, 0, 0)
  line L0 (-23, 35) -> (-30.3921, 43.8095)
  line L1 (-30.3921, 43.8095) -> (-35.3921, 43.8095)
  line L2 (-35.3921, 43.8095) -> (-52.6735, 23.2143)
  line L3 (-52.6735, 23.2143) -> (-52.6735, -23.2143)
  line L4 (-52.6735, -23.2143) -> (-35.3921, -43.8095)
  line L5 (-35.3921, -43.8095) -> (-30.3921, -43.8095)
  line L6 (-30.3921, -43.8095) -> (-23, -35)
  line L7 (-23, -35) -> (-23, -19.5768)
  line L8 (-23, -19.5768) -> (-23, 19.5768)
  line L9 (-23, 19.5768) -> (-23, 35)
  line L10 (-32.8921, 43.8095) -> (-32.8921, 40.8095)
  circle A0 centre (-32.8921, 40.8095) radius 1.5
  dimension "d17" = 3
  dimension "d18" = 3
  constraint midpoint L1 L10.start
  constraint perpendicular L1 L10
  constraint coincident L10.end A0.centre
  measures "d17" distance of L10.start L10.end
  measures "d18" diameter of A0
extrude "Extrusion4" cut sketch "Esquisse4" against normal blind 12 contours A0
mirror "Symétrie miroir1" about plane through (0, 0, 0) normal (0, 1, 0) of "Extrusion4"
mirror "Symétrie miroir2" about plane through (0, 0, 0) normal (0, 0, 1) of "Extrusion3", "Extrusion4", "Symétrie miroir1"
sketch "Esquisse5" plane through (23, 0, 0) normal (1, 0, 0) x (0, 1, 0)
  line L0 (-19.5768, 13) -> (19.5768, 13)
  arc A0 (19.5768, 13) -> (-19.5768, 13) centre (0, 0) ccw
  line L1 (0, 13) -> (0, 23.5)
  line L2 (0, 13) -> (-1, 13)
  line L3 (-1, 13) -> (-1, 22)
  line L4 (-1, 22) -> (1, 22)
  line L5 (1, 22) -> (1, 13)
  dimension "d25" = 1
  dimension "d26" = 9
  dimension "d27" = 2
  constraint midpoint L0 L1.start
  constraint midpoint A0 L1.end
  constraint perpendicular L1 L2
  constraint perpendicular L0 L3
  constraint perpendicular L1 L4
  constraint coincident L0 L5.end
  constraint perpendicular L0 L5
  measures "d25" distance of L1.start L2.end
  measures "d26" distance of L2.end L3.end
  measures "d27" distance of L3.end L4.end
extrude "Extrusion5" add sketch "Esquisse5" along normal blind 3 contours L0 L1 L2 L3 L4 | L0 L1 L4 L5
fillet "Congé1" radius 1 2 edges at (24.5, -1, 22) (24.5, 1, 22)
mirror "Symétrie miroir3" about plane through (0, 0, 0) normal (0, 0, 1) of "Extrusion5", "Congé1"
sketch "Esquisse6" plane through (52.6735, 0, 0) normal (1, 0, 0) x (0, 1, 0)
  line L0 (23.2143, 13) -> (-23.2143, 13)
  line L1 (-23.2143, 13) -> (-23.2143, 9)
  line L2 (-23.2143, 9) -> (23.2143, 9)
  line L3 (23.2143, 9) -> (23.2143, 13)
  line L4 (8, -13) -> (-8, -13)
  line L5 (-8, -13) -> (-8, 13)
  line L6 (-8, 13) -> (8, 13)
  line L7 (8, 13) -> (8, -13)
  line L8 (8, -13) -> (-8, 13) construction
  line L9 (-8, -13) -> (8, 13) construction
  dimension "d34" = 16
  dimension "d35" = 26
  constraint horizontal L4
  constraint perpendicular L4 L5
  constraint parallel L4 L6
  constraint parallel L5 L7
  constraint coincident L8 origin
  constraint coincident L9 origin
  measures "d34" distance of L5.end L6.end
  measures "d35" distance of L4.end L5.end
extrude "Extrusion6" add sketch "Esquisse6" along normal blind 3 contours L0 L2 L5 L6 L7 | L2 L4 L5 L7
sketch "Esquisse7" plane through (0, 0, 0) normal (-1, 0, 0) x (0, -1, 0)
  circle A0 centre (0, 0) radius 35
  circle A1 centre (0, 0) radius 10
  dimension "d38" = 20
  constraint coincident A0.centre A1.centre
  measures "d38" diameter of A1
extrude "Extrusion7" cut sketch "Esquisse7" against normal blind 10 contours A1
equation "d4 = ( 23.5 * 2 ) * 1 mm"

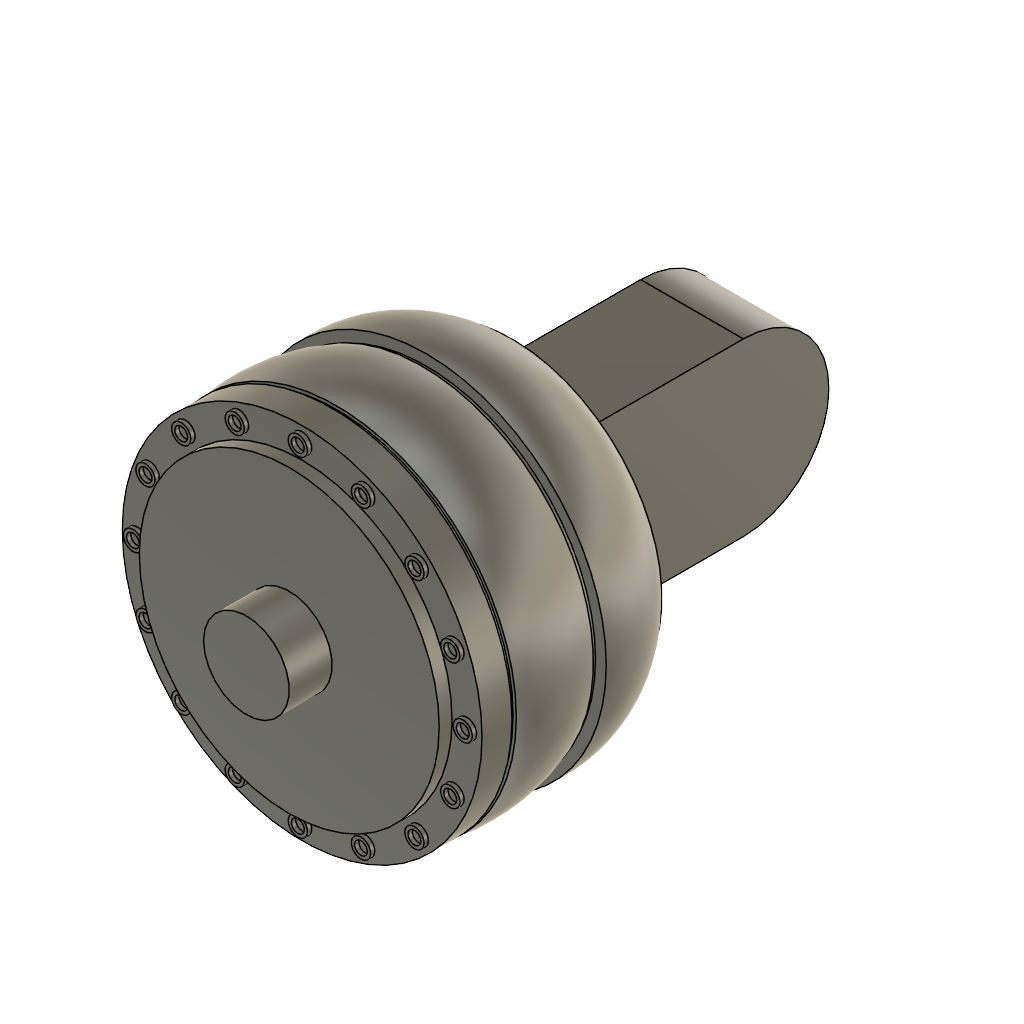
design "jaw5"
part number: 2026-11-17-17-52-57-447
Autodesk Fusion 360 part; units mm, degrees
sketch "Esquisse1" plane through (0, 0, 0) normal (0, 0, 1) x (1, 0, 0)
  line L0 (0, 0) -> (-35, 0)
  line L1 (0, 0) -> (0, -20)
  line L2 (0, -20) -> (-42, -20)
  arc A0 (-35, 0) -> (-42, -20) centre (-17.1273, -17.4804) ccw
  dimension "d1" = 35
  dimension "d2" = 20
  dimension "d3" = 42
  dimension "d4" = 25
  constraint coincident L0.start L1.start
  constraint horizontal L0
  constraint perpendicular L0 L1
  constraint perpendicular L1 L2
  measures "d1" distance of L0.start L0.end
  measures "d2" distance of L0.start L1.end
  measures "d3" distance of L1.end L2.end
  measures "d4" radius of A0
revolve "Révolution1" add sketch "Esquisse1" angle 360 about axis through (0, 0, 0) along (0, -1, 0)
sketch "Esquisse2" plane through (0, -20, 0) normal (0, -1, 0) x (1, 0, 0)
  circle A0 centre (0, 0) radius 42
  circle A1 centre (0, 0) radius 39.5
  dimension "d6" = 79
  constraint concentric A0 A1
  measures "d6" diameter of A1
extrude "Extrusion1" add sketch "Esquisse2" along normal blind 1 contours A1
sketch "Esquisse3" plane through (0, 0, 0) normal (0, 0, 1) x (1, 0, 0)
  line L0 (-39.5, -21) -> (39.5, -21)
  line L1 (0, -21) -> (0, -41)
  line L2 (0, -21) -> (-40, -21)
  line L3 (0, -41) -> (-42, -41)
  arc A0 (-40, -21) -> (-42, -41) centre (-5.5677, -34.5432) ccw
  dimension "d9" = 20
  dimension "d10" = 40
  dimension "d11" = 37
  constraint midpoint L0 L1.start
  constraint perpendicular L0 L1
  constraint perpendicular L1 L2
  constraint perpendicular L1 L3
  measures "d9" distance of L1.start L1.end
  measures "d10" distance of L1.start L2.end
  measures "d11" radius of A0
revolve "Révolution2" add sketch "Esquisse3" angle 360 about axis through (0, -21, 0) along (0, -1, 0)
sketch "Esquisse4" plane through (0, -41, 0) normal (0, -1, 0) x (1, 0, 0)
  circle A0 centre (0, 0) radius 42
  circle A1 centre (0, 0) radius 41.25
  dimension "d13" = 82.5
  constraint coincident A0.centre A1.centre
  measures "d13" diameter of A1
extrude "Extrusion2" add sketch "Esquisse4" along normal blind 1 contours A1
sketch "Esquisse5" plane through (0, -42, 0) normal (0, -1, 0) x (1, 0, 0)
  circle A0 centre (0, 0) radius 41.25
  circle A1 centre (0, 0) radius 42
  dimension "d16" = 84
  constraint concentric A0 A1
  measures "d16" diameter of A1
extrude "Extrusion3" add sketch "Esquisse5" along normal blind 7 contours A0 | A1
sketch "Esquisse6" plane through (0, -49, 0) normal (0, -1, 0) x (1, 0, 0)
  circle A0 centre (0, 0) radius 42
  circle A1 centre (0, 0) radius 35
  dimension "d19" = 70
  constraint coincident A0.centre A1.centre
  measures "d19" diameter of A1
extrude "Extrusion4" add sketch "Esquisse6" along normal blind 3 contours A1
sketch "Esquisse7" plane through (0, -49, 0) normal (0, -1, 0) x (1, 0, 0)
  circle A0 centre (0, 0) radius 35
  circle A1 centre (0, 0) radius 42
  line L0 (0, 0) -> (35, 0)
  line L1 (35, 0) -> (42, 0)
  circle A2 centre (38.5, 0) radius 2.25
  circle A3 centre (38.5, 0) radius 1.5
  dimension "d22" = 4.5
  dimension "d23" = 3
  constraint coincident A0.centre A1.centre
  constraint coincident A0 L0.end
  constraint horizontal L0
  constraint coincident A1 L1.end
  constraint perpendicular A1 L1
  constraint midpoint L1 A2.centre
  constraint concentric A2 A3
  measures "d22" diameter of A2
  measures "d23" diameter of A3
extrude "Extrusion5" add sketch "Esquisse7" along normal blind 1 contours L1 A2 A3 | L1 A2 A3
pattern_circular "Réseau C1" count 16 over 360 about axis through (0, -52, 0) along (0, -1, 0) of "Extrusion5"
sketch "Esquisse8" plane through (0, 0, 0) normal (0, 1, 0) x (-1, 0, 0)
  circle A0 centre (0, 0) radius 35
  line L0 (12, -20) -> (-12, -20)
  line L1 (-12, -20) -> (-12, 20)
  line L2 (-12, 20) -> (12, 20)
  line L3 (12, 20) -> (12, -20)
  line L4 (12, -20) -> (-12, 20) construction
  line L5 (-12, -20) -> (12, 20) construction
  dimension "d28" = 24
  dimension "d29" = 40
  constraint horizontal L0
  constraint perpendicular L0 L1
  constraint parallel L0 L2
  constraint parallel L1 L3
  constraint coincident L4 A0.centre
  constraint coincident L5 A0.centre
  constraint coincident A0.centre origin
  measures "d28" distance of L1.end L2.end
  measures "d29" distance of L0.end L1.end
extrude "Extrusion6" add sketch "Esquisse8" along normal blind 42 contours L0 L1 L2 L3
sketch "Esquisse9" plane through (12, 0, 0) normal (1, 0, 0) x (0, 1, 0)
  line L0 (0, 20) -> (0, -20)
  line L1 (0, -20) -> (42, -20)
  line L2 (42, -20) -> (42, 20)
  line L3 (42, 20) -> (0, 20)
  circle A0 centre (42, 0) radius 20
  constraint midpoint L2 A0.centre
  constraint coincident L1.end A0
extrude "Extrusion7" add sketch "Esquisse9" against normal blind 24 contours L2 A0 picked at (49.5476, 0.8809)
sketch "Esquisse10" plane through (-12, 0, 0) normal (-1, 0, 0) x (0, -1, 0)
  line L0 (0, -20) -> (0, 20)
  line L1 (0, 20) -> (-42, 20)
  arc A0 (-42, 20) -> (-42, -20) centre (-42, 0) ccw
  line L2 (-42, -20) -> (0, -20)
  circle A1 centre (-42, 0) radius 10
  dimension "d34" = 20
  constraint concentric A0 A1
  measures "d34" diameter of A1
extrude "Extrusion8" add sketch "Esquisse10" along normal blind 10 contours A1
sketch "Esquisse11" plane through (0, -52, 0) normal (0, -1, 0) x (1, 0, 0)
  circle A0 centre (0, 0) radius 35
  circle A1 centre (0, 0) radius 10
  dimension "d37" = 20
  constraint concentric A0 A1
  measures "d37" diameter of A1
extrude "Extrusion9" add sketch "Esquisse11" along normal blind 10 contours A1

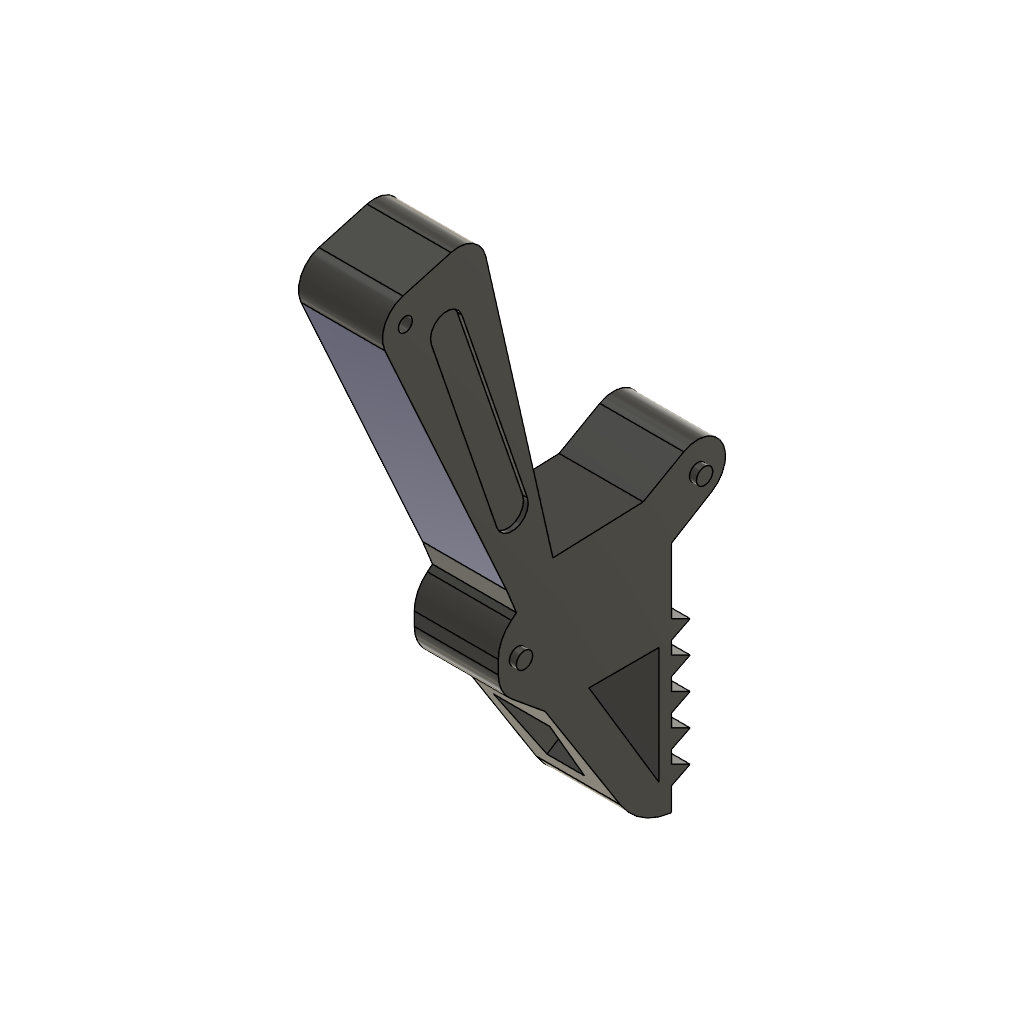
design "jaw7"
part number: 2026-11-18-09-22-13-996
Autodesk Fusion 360 part; units mm, degrees
sketch "Esquisse1" plane through (0, 0, 0) normal (1, 0, 0) x (0, 1, 0)
  line L0 (216.6597, -23.0876) -> (187.7386, 40.6586)
  line L1 (187.7386, 40.6586) -> (210.8459, 47.1435)
  line L2 (210.8459, 47.1435) -> (226.596, -22.0875)
  line L3 (226.596, -22.0875) -> (218.7953, -28.3445)
  line L4 (218.7953, -28.3445) -> (216.6597, -23.0876)
  line L5 (218.7953, -28.3445) -> (214.8949, -31.4729)
  line L6 (214.8949, -31.4729) -> (214.8949, -41.4729)
  line L7 (214.8949, -41.4729) -> (224.9331, -49.7335)
  line L8 (224.9331, -49.7335) -> (241.0093, -75.0624)
  line L9 (241.0093, -75.0624) -> (241.0093, -82.0624)
  line L10 (241.0093, -82.0624) -> (252.0093, -82.0624)
  line L11 (252.0093, -82.0624) -> (252.0093, -32.0624)
  line L12 (252.0093, -32.0624) -> (260.5495, -26.8601)
  line L13 (226.596, -22.0875) -> (245.9143, -21.3694)
  line L14 (245.9143, -21.3694) -> (254.6108, -16.4326)
  arc A0 (260.5495, -26.8601) -> (254.6108, -16.4326) centre (257.5802, -21.6463) ccw
  dimension "d1" = 70
  dimension "d2" = 71
  dimension "d3" = 24
  dimension "d4" = 10
  dimension "d5" = 15
  dimension "d6" = 10
  dimension "d7" = 13
  dimension "d8" = 30
  dimension "d9" = 7
  dimension "d10" = 11
  dimension "d11" = 50
  dimension "d12" = 10
  dimension "d13" = 10
  dimension "d15" = 12
  constraint parallel L3 L5
  constraint vertical L6
  constraint vertical L9
  constraint perpendicular L9 L10
  constraint perpendicular L10 L11
  measures "d1" distance of L0.start L0.end
  measures "d2" distance of L1.end L2.end
  measures "d3" distance of L0.end L1.end
  measures "d4" distance of L2.end L3.end
  measures "d5" distance of L2.end L5.end
  measures "d6" distance of L5.end L6.end
  measures "d7" distance of L6.end L7.end
  measures "d8" distance of L7.end L8.end
  measures "d9" distance of L8.end L9.end
  measures "d10" distance of L9.end L10.end
  measures "d11" distance of L10.end L11.end
  measures "d12" distance of L11.end L12.end
  measures "d13" distance of L13.end L14.end
  measures "d15" distance of L12.end L14.end
extrude "Extrusion1" add sketch "Esquisse1" along normal mid plane 18
sketch "Esquisse2" plane through (9, 0, 0) normal (1, 0, 0) x (0, 1, 0)
  line L0 (218.7953, -28.3445) -> (214.8949, -31.4729)
  line L1 (214.8949, -31.4729) -> (214.8949, -41.4729)
  line L2 (214.8949, -41.4729) -> (224.9331, -49.7335)
  line L3 (224.9331, -49.7335) -> (241.0093, -75.0624)
  line L4 (241.0093, -75.0624) -> (241.0093, -82.0624)
  line L5 (241.0093, -82.0624) -> (252.0093, -82.0624)
  line L6 (252.0093, -82.0624) -> (252.0093, -32.0624)
  line L7 (252.0093, -32.0624) -> (260.5495, -26.8601)
  arc A0 (260.5495, -26.8601) -> (254.6108, -16.4326) centre (257.5802, -21.6463) ccw
  line L8 (254.6108, -16.4326) -> (245.9143, -21.3694)
  line L9 (245.9143, -21.3694) -> (226.596, -22.0875)
  line L10 (226.596, -22.0875) -> (210.8459, 47.1435)
  line L11 (210.8459, 47.1435) -> (187.7386, 40.6586)
  line L12 (187.7386, 40.6586) -> (216.6597, -23.0876)
  line L13 (216.6597, -23.0876) -> (218.7953, -28.3445)
  line L14 (241.0093, -75.0624) -> (249.3093, -75.0624)
  line L15 (249.3093, -75.0624) -> (249.3093, -50.0624)
  line L16 (249.3093, -50.0624) -> (234.3093, -50.0624)
  line L17 (234.3093, -50.0624) -> (249.3093, -75.0624)
  dimension "d18" = 25
  dimension "d19" = 2.7
  constraint coincident L3.end L4.start
  constraint perpendicular L6 L14
  constraint perpendicular L14 L15
  constraint perpendicular L15 L16
  measures "d18" distance of L14.end L15.end
  measures "d19" distance of L6 L15
extrude "Extrusion2" cut sketch "Esquisse2" against normal blind 55 contours L15 L16 L17
sketch "Esquisse3" plane through (9, 0, 0) normal (1, 0, 0) x (0, 1, 0)
  line L0 (249.3093, -50.0624) -> (249.3093, -75.0624)
  line L1 (249.3093, -75.0624) -> (234.3093, -50.0624)
  line L2 (234.3093, -50.0624) -> (249.3093, -50.0624)
  line L3 (218.7953, -28.3445) -> (214.8949, -31.4729)
  line L4 (214.8949, -31.4729) -> (214.8949, -41.4729)
  line L5 (214.8949, -41.4729) -> (224.9331, -49.7335)
  line L6 (224.9331, -49.7335) -> (241.0093, -75.0624)
  line L7 (241.0093, -75.0624) -> (241.0093, -82.0624)
  line L8 (241.0093, -82.0624) -> (252.0093, -82.0624)
  line L9 (252.0093, -82.0624) -> (252.0093, -32.0624)
  line L10 (252.0093, -32.0624) -> (260.5495, -26.8601)
  arc A0 (260.5495, -26.8601) -> (254.6108, -16.4326) centre (257.5802, -21.6463) ccw
  line L11 (254.6108, -16.4326) -> (245.9143, -21.3694)
  line L12 (245.9143, -21.3694) -> (226.596, -22.0875)
  line L13 (226.596, -22.0875) -> (210.8459, 47.1435)
  line L14 (210.8459, 47.1435) -> (187.7386, 40.6586)
  line L15 (187.7386, 40.6586) -> (216.6597, -23.0876)
  line L16 (216.6597, -23.0876) -> (218.7953, -28.3445)
  line L17 (252.0093, -82.0624) -> (252.0093, -77.0624)
  line L18 (252.0093, -77.0624) -> (252.0093, -73.0624)
  line L19 (252.0093, -75.0624) -> (256.0093, -75.0624)
  line L20 (252.0093, -73.0624) -> (256.0093, -75.0624)
  line L21 (256.0093, -75.0624) -> (252.0093, -77.0624)
  dimension "d22" = 5
  dimension "d23" = 4
  dimension "d24" = 4
  constraint coincident L8.end L9.start
  constraint perpendicular L8 L17
  constraint parallel L9 L18
  constraint midpoint L18 L19.start
  constraint perpendicular L9 L19
  measures "d22" distance of L8.end L17.end
  measures "d23" distance of L17.end L18.end
  measures "d24" distance of L19.start L19.end
extrude "Extrusion3" add sketch "Esquisse3" against normal up to surface (18 mm away) contours L9 L18 L19 L21 | L9 L18 L19 L20
pattern_linear "Réseau R1" count 5 spacing 6.75 along (0, 0, 1) of 2 faces at (-3, 254.6759, -75.7291) (3, 253.3426, -73.7291)
fillet "Congé1" radius 6 2 edges at (0, 210.8459, 47.1435) (0, 187.7386, 40.6586)
fillet "Congé2" radius 15 1 edges at (0, 241.0093, -82.0624)
fillet "Congé3" radius 7.5 2 edges at (0, 214.8949, -31.4729) (0, 214.8949, -41.4729)
sketch "Esquisse4" plane through (9, 0, 0) normal (1, 0, 0) x (0, 1, 0)
  arc A0 (214.8949, -37.9318) -> (217.6293, -43.723) centre (222.3949, -37.9318) ccw
  line L0 (217.6293, -43.723) -> (224.9331, -49.7335)
  line L1 (224.9331, -49.7335) -> (241.0093, -75.0624)
  arc A1 (241.0093, -75.0624) -> (252.0093, -82.0624) centre (253.7621, -67.1652) ccw
  line L2 (252.0093, -82.0624) -> (252.0093, -77.0624)
  line L3 (252.0093, -77.0624) -> (256.0093, -75.0624)
  line L4 (256.0093, -75.0624) -> (252.0093, -73.0624)
  line L5 (252.0093, -73.0624) -> (252.0093, -70.3124)
  line L6 (252.0093, -70.3124) -> (256.0093, -68.3124)
  line L7 (256.0093, -68.3124) -> (252.0093, -66.3124)
  line L8 (252.0093, -66.3124) -> (252.0093, -63.5624)
  line L9 (252.0093, -63.5624) -> (256.0093, -61.5624)
  line L10 (256.0093, -61.5624) -> (252.0093, -59.5624)
  line L11 (252.0093, -59.5624) -> (252.0093, -56.8124)
  line L12 (252.0093, -56.8124) -> (256.0093, -54.8124)
  line L13 (256.0093, -54.8124) -> (252.0093, -52.8124)
  line L14 (252.0093, -52.8124) -> (252.0093, -50.0624)
  line L15 (252.0093, -50.0624) -> (256.0093, -48.0624)
  line L16 (256.0093, -48.0624) -> (252.0093, -46.0624)
  line L17 (252.0093, -46.0624) -> (252.0093, -32.0624)
  line L18 (252.0093, -32.0624) -> (260.5495, -26.8601)
  arc A2 (260.5495, -26.8601) -> (254.6108, -16.4326) centre (257.5802, -21.6463) ccw
  line L19 (254.6108, -16.4326) -> (245.9143, -21.3694)
  line L20 (245.9143, -21.3694) -> (226.596, -22.0875)
  line L21 (226.596, -22.0875) -> (212.245, 40.9935)
  arc A3 (212.245, 40.9935) -> (204.7733, 45.4393) centre (206.3945, 39.6625) ccw
  line L22 (204.7733, 45.4393) -> (194.4698, 42.5477)
  arc A4 (194.4698, 42.5477) -> (190.6271, 34.2919) centre (196.0911, 36.7709) ccw
  line L23 (190.6271, 34.2919) -> (216.6597, -23.0876)
  line L24 (216.6597, -23.0876) -> (218.7953, -28.3445)
  line L25 (218.7953, -28.3445) -> (217.7022, -29.2212)
  arc A5 (217.7022, -29.2212) -> (214.8949, -35.0717) centre (222.3949, -35.0717) ccw
  line L26 (214.8949, -35.0717) -> (214.8949, -37.9318)
  line L27 (249.3093, -75.0624) -> (234.3093, -50.0624)
  line L28 (234.3093, -50.0624) -> (249.3093, -50.0624)
  line L29 (249.3093, -50.0624) -> (249.3093, -75.0624)
  circle A6 centre (195, 37) radius 1.5
  dimension "d37" = 3
  measures "d37" diameter of A6
extrude "Extrusion4" cut sketch "Esquisse4" against normal blind 35 contours A6